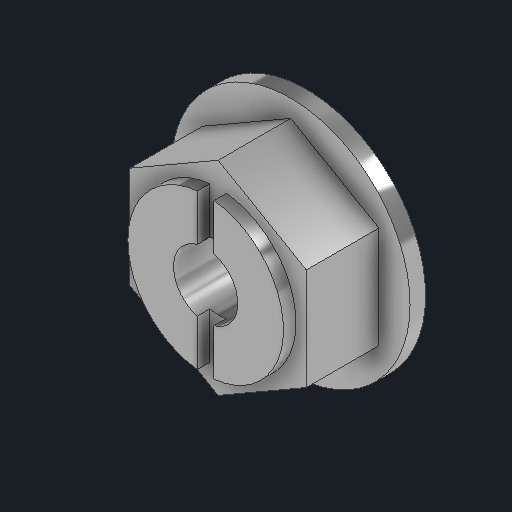
# Autodesk Inventor part: worm_nut_17AF
Saved by Autodesk Inventor 2027.1 (Build 311270010, 270A)
## iProperties
Created: 2026-11-03
Part Number: worm_nut_17AF
Material: Generic
Description: Worm bearing nut 17 mm AF (measured) with slotted collar, on a 23 mm washer
Document SubType Name: Modeling
Designer: Claude (from photos)
Density: 1 g/cm^3
Appearance: Stainless Steel - Bright
Author: alexg
Autodesk Inventor part; units mm, degrees
sketch "Washer 23 sketch" plane through (0, 0, 0) normal (0, 0, 1) x (1, 0, 0)
  circle A0 centre (0, 0) radius 11.5
  circle A1 centre (0, 0) radius 3.1
  constraints: 2 centre point
extrude "Washer 23" add sketch "Washer 23 sketch" along normal blind 1.5
ref_plane "Work Plane1" through (0, 0, 1.5) normal (0, 0, 1) x (1, 0, 0)
sketch "Hex nut 17 AF sketch" plane through (0, 0, 1.5) normal (0, 0, 1) x (1, 0, 0)
  line L0 (8.5, 4.9075) -> (0, 9.815)
  line L1 (0, 9.815) -> (-8.5, 4.9075)
  line L2 (-8.5, 4.9075) -> (-8.5, -4.9075)
  line L3 (-8.5, -4.9075) -> (0, -9.815)
  line L4 (0, -9.815) -> (8.5, -4.9075)
  line L5 (8.5, -4.9075) -> (8.5, 4.9075)
  circle A0 centre (0, 0) radius 3.1
  constraints: 12 end point, 1 centre point
extrude "Hex nut 17 AF" add sketch "Hex nut 17 AF sketch" along normal blind 7
ref_plane "Work Plane2" through (0, 0, 8.5) normal (0, 0, 1) x (1, 0, 0)
sketch "Slotted collar sketch" plane through (0, 0, 8.5) normal (0, 0, 1) x (1, 0, 0)
  circle A0 centre (0, 0) radius 7.5
  circle A1 centre (0, 0) radius 3.1
  constraints: 2 centre point
extrude "Slotted collar" add sketch "Slotted collar sketch" along normal blind 1.2
ref_plane "Work Plane3" through (0, 0, 9.7) normal (0, 0, 1) x (1, 0, 0)
sketch "Collar slot sketch" plane through (0, 0, 9.7) normal (0, 0, 1) x (1, 0, 0)
  line L0 (-0.8, -8) -> (0.8, -8)
  line L1 (0.8, -8) -> (0.8, 8)
  line L2 (0.8, 8) -> (-0.8, 8)
  line L3 (-0.8, 8) -> (-0.8, -8)
  constraints: 8 end point, 2 parallel, 1 horizontal, 1 perpendicular
extrude "Collar slot" cut sketch "Collar slot sketch" against normal blind 1.2
body "Solid1"
